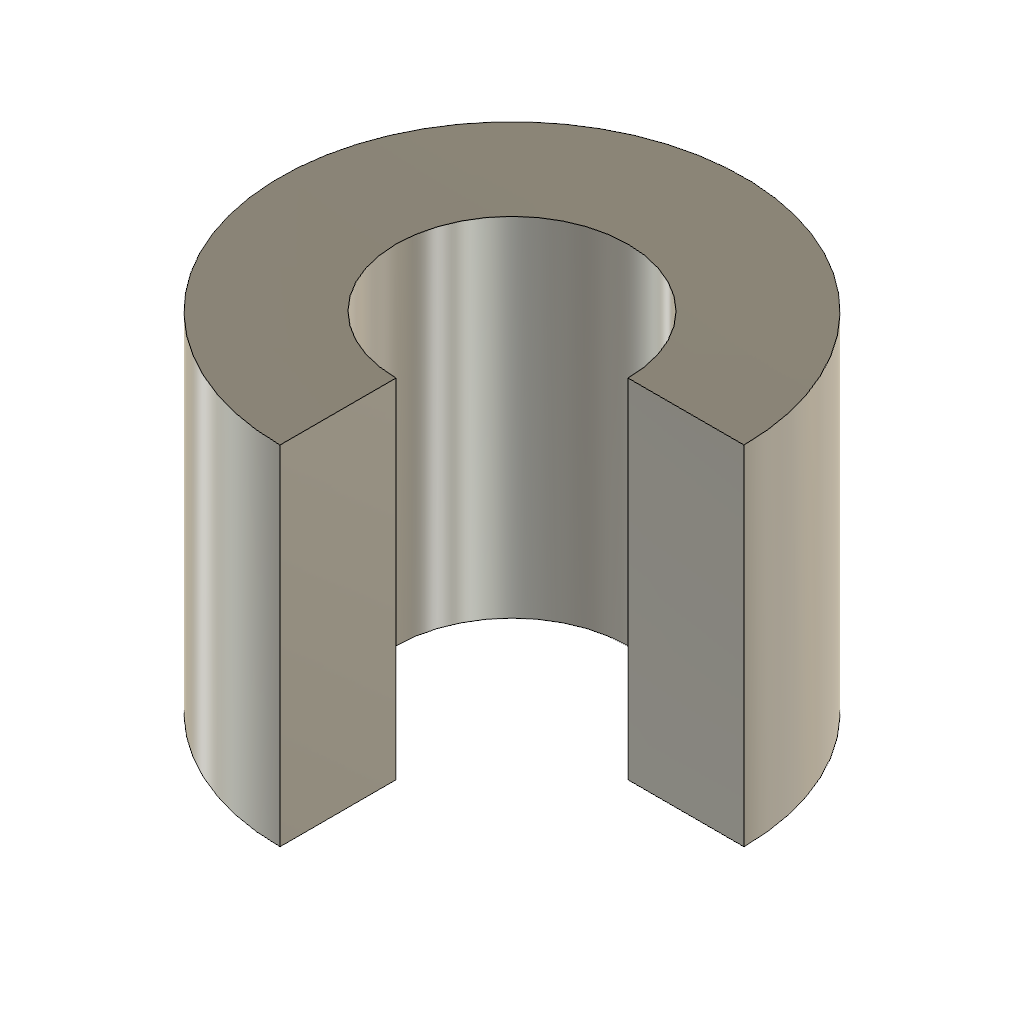
vendor_RevolveFull (Autodesk Fusion 360 design; units mm, degrees)
Autodesk Fusion 360 part; units mm, degrees
sketch "Revolve sketch" plane through (0, 0, 0) normal (0, 1, 0) x (1, 0, 0)
  line L0 (10, 0) -> (20, 0)
  line L1 (20, 0) -> (20, -30)
  line L2 (20, -30) -> (10, -30)
  line L3 (10, -30) -> (10, 0)
revolve "Tube revolve" add sketch "Revolve sketch" angle 270 about axis through (0, 0, 0) along (0, 0, 1)
equation "height = 20.0 mm"
